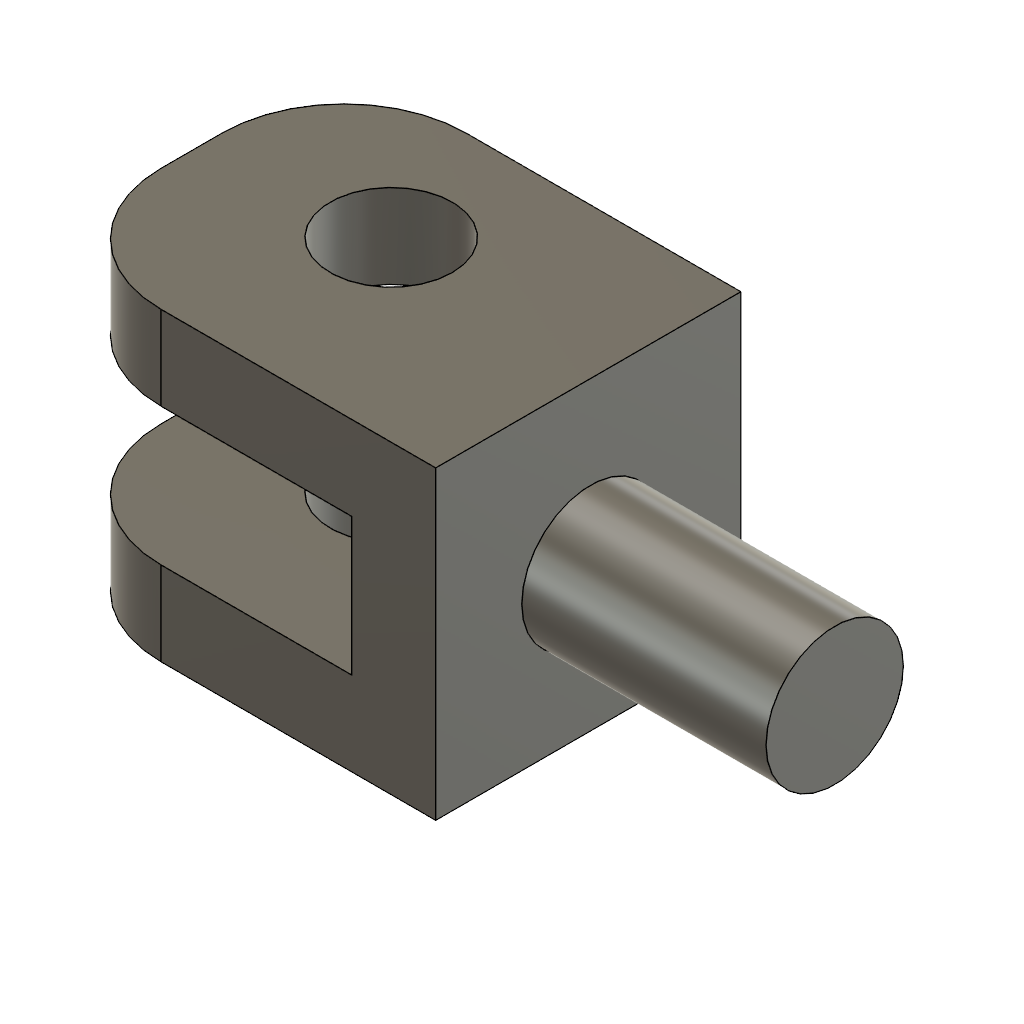
Ex.No.3.1 (Autodesk Fusion 360 design; units mm, degrees)
part number: 2026-10-09-15-26-09-455
Autodesk Fusion 360 part; units mm, degrees
sketch "Sketch1" plane through (0, 0, 0) normal (0, 0, 1) x (1, 0, 0)
  line L0 (-127.1588, 74.6071) -> (-75.1588, 74.6071)
  line L1 (-75.1588, 74.6071) -> (-75.1588, 34.6071)
  line L2 (-127.1588, 34.6071) -> (-75.1588, 34.6071)
  line L3 (-127.1588, 74.6071) -> (-127.1588, 63.6071)
  line L4 (-127.1588, 34.6071) -> (-127.1588, 45.6071)
  line L5 (-127.1588, 63.6071) -> (-86.1588, 63.6071)
  line L6 (-127.1588, 45.6071) -> (-86.1588, 45.6071)
  line L7 (-86.1588, 63.6071) -> (-86.1588, 45.6071)
  dimension "d1" = 52
  dimension "d2" = 40
  dimension "d3" = 52
  dimension "d4" = 11
  dimension "d5" = 11
  dimension "d6" = 41
  dimension "d7" = 41
  constraint horizontal L0
  constraint perpendicular L0 L1
  constraint horizontal L2
  constraint perpendicular L0 L3
  constraint perpendicular L2 L4
  constraint perpendicular L3 L5
  constraint perpendicular L4 L6
  measures "d1" distance of L0.start L0.end
  measures "d2" distance of L0.end L1.end
  measures "d3" distance of L1.end L2.start
  measures "d4" distance of L0.start L3.end
  measures "d5" distance of L2.start L4.end
  measures "d6" distance of L3.end L5.end
  measures "d7" distance of L4.end L6.end
extrude "Extrude1" add sketch "Sketch1" along normal blind 40
sketch "Sketch2" plane through (-75.1588, 0, 0) normal (1, 0, 0) x (0, 0, -1)
  line L0 (0, 34.6071) -> (0, 74.6071)
  line L1 (0, 74.6071) -> (-40, 74.6071)
  line L2 (-40, 74.6071) -> (-40, 34.6071)
  line L3 (-40, 34.6071) -> (0, 34.6071)
  circle A0 centre (-19.7155, 53.5083) radius 9
  dimension "d10" = 18
  measures "d10" diameter of A0
extrude "Extrude2" add sketch "Sketch2" along normal blind 32 contours A0
sketch "Sketch3" plane through (0, 74.6071, 0) normal (0, 1, 0) x (-1, 0, 0)
  line L0 (75.1588, 0) -> (127.1588, 0)
  line L1 (127.1588, 0) -> (127.1588, 40)
  line L2 (127.1588, 40) -> (75.1588, 40)
  line L3 (75.1588, 40) -> (75.1588, 0)
  circle A0 centre (104.2356, 16.748) radius 8
  dimension "d13" = 16
  measures "d13" diameter of A0
extrude "Extrude3" cut sketch "Sketch3" against normal blind 40 contours A0
fillet "Fillet1" radius 16 1 edges at (-127.1588, 69.1071, 40)
fillet "Fillet2" radius 16 1 edges at (-127.1588, 40.1071, 40)
fillet "Fillet3" radius 16 1 edges at (-127.1588, 69.1071, 0)
fillet "Fillet4" radius 16 1 edges at (-127.1588, 40.1071, 0)
